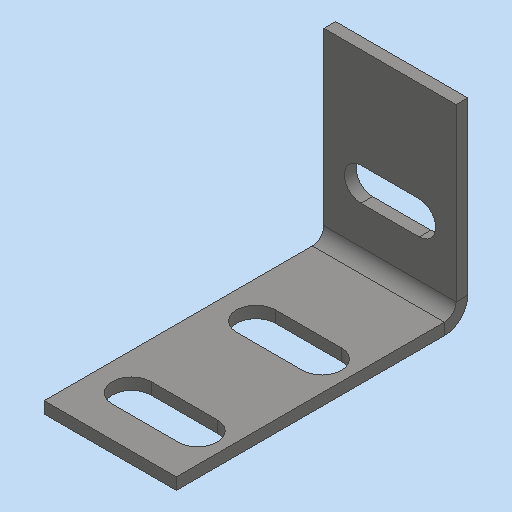
# Autodesk Inventor part: MM0861AN200_G22_108
Saved by Autodesk Inventor 2023.3 (Build 273359000, 359)
## iProperties
Part Number: MM0861AN200_G22_108
Material: 1.4301 X5CrNi18-10
Description: =<RBPARTNOTITLE2>
Document SubType Name: Blech
Designer: Benutzer
Mass: 80.0937 g
Surface Area: 82.8903 cm^2
Volume: 10.203 cm^3
Density: 7.85 g/cm^3
Sheet Metal Rule: Standard_mm
Appearance: Stahl - rostfrei AnP
Vendor: ASW
Flat Pattern Width: 3.4 cm
Flat Pattern Length: 11.9786 cm
Flat Pattern Area: 40.7272 cm^2
Sheet Metal Width: 34,000 mm
Sheet Metal Length: 119,786 mm
Sheet Metal Area: 4072,719 mm^2
RBCHANGEDESCRIPTION1: Erstfreigabe
RBCHANGENO1: 00
RBDOCUMENTTYPE: DRF
RBDOCUMENTVERSION: 00
RBDRAWINGMAINSCALE: 1:1
RBDRAWINGMISSINGSPEC: --
RBDRAWINGVOLUME: --
RBDSV1: 0850
RBGBDETAILS: 43274
RBGBEDGESIN1: +0,5
RBGBEDGESIN2: +0,2
RBGBEDGESOUT1: -0,3
RBGBEDGESOUT2: -0,1
RBMATERIAL: =<Material>
RBMATMEETS: --
RBMATNO: =<Part Number>
RBORGUNITRESPONSIBLE1: AnP/TEF1
RBPARTMADEOF: 50 x 75 x 34 (FM)
RBPARTNO: SIEHE MNR
RBPARTNOTITLE1: manufactured part
RBPARTNOTITLE2: Anfertigungsteil
RBPARTSAFETYINDICATOR: --
RBSURFACE: --
RBSURFACE2: --
RBZEDGESNORM: ISO13715:2002-06
RBZGENDIMCLASS: m
RBZGENDIMNORM: ISO 2768-1:1989-11
RBZGENGEOCLASS: H
RBZGENGEONORM: ISO 2768-2:1989-11
RBZSURFACENORM: ISO13D2:2002-02
RBZTOLERANCENORM: ISO 14405-1:2010-12
AnP_Material: =<Material>
AnP_TemplVers: 20190222
AnP_Kategorie: 1
MaxAbmaße: 50 x 75 x 34 (FM)
Author: Benutzer
Keywords: =<RBPARTMADEOF>
Comments: =<RBSURFACE2>
Revision Number: 01
Autodesk Inventor part; units mm, degrees
ref_plane "YZ Plane" through (0, 0, 0) normal (1, 0, 0) x (0, 1, 0)
ref_plane "XZ Plane" through (0, 0, 0) normal (0, 1, 0) x (-1, 0, 0)
ref_plane "XY Plane" through (0, 0, 0) normal (0, 0, 1) x (1, 0, 0)
sketch "Skizze1" plane through (0, 0, 0) normal (0, 0, 1) x (1, 0, 0)
  line L0 (0, 0) -> (34, 0)
  line L1 (34, 0) -> (34, 75)
  line L2 (34, 75) -> (0, 75)
  line L3 (0, 75) -> (0, 0)
  dimension "d0" = 34
  dimension "d1" = 75
  constraints: 8 end point, 2 parallel, 1 horizontal, 1 perpendicular
  measures "d0" distance of L2.end L1.end
  measures "d1" distance of L1.end L0.end
extrude "Extrusion1" add sketch "Skizze1" along normal blind 3
sketch "Skizze2" plane through (0, 72, 0) normal (0, 1, 0) x (-1, 0, 0)
  line L0 (-34, 0) -> (0, 0)
  line L1 (0, 0) -> (0, 50)
  line L2 (0, 50) -> (-34, 50)
  line L3 (-34, 50) -> (-34, 0)
  constraints: 4 end point, 4 other
edge flange "Lasche1" height 50 angle 90 thickness 3 bend radius 3 thickness toward (0, 1, 0) relief tear relief width 3 relief depth 1.5 edges at (17, 75, 3) wall of the first edge with corners at (34, 72, 0) (0, 72, 0) (0, 72, 50) (34, 72, 50)
bend "Biegung1"
corner "Ecke1"
sketch "Skizze4" plane through (0, 0, 3) normal (0, 0, 1) x (1, 0, 0)
  line L0 (26.5, 45) -> (9.5, 45) construction
  line L1 (26.5, 50) -> (9.5, 50)
  line L2 (9.5, 40) -> (26.5, 40)
  arc A0 (26.5, 40) -> (26.5, 50) centre (26.5, 45) ccw
  arc A1 (9.5, 50) -> (9.5, 40) centre (9.5, 45) ccw
  line L3 (26.5, 13) -> (9.5, 13) construction
  line L4 (26.5, 18) -> (9.5, 18)
  line L5 (9.5, 8) -> (26.5, 8)
  arc A2 (26.5, 8) -> (26.5, 18) centre (26.5, 13) ccw
  arc A3 (9.5, 18) -> (9.5, 8) centre (9.5, 13) ccw
  line L6 (34, 0) -> (34, 69) projected
  point P0 (0, 0)
  point P1 (18, 45)
  point P2 (18, 13)
  dimension "d20" = 17
  dimension "d21" = 10
  dimension "d22" = 10
  dimension "d23" = 16
  constraints: 16 end point, 8 point on circle, 8 tangent, 4 centre point, 3 parallel, 2 midpoint, 2 vertical alignment, 1 horizontal
  measures "d20" distance of L0.start L0.end
  measures "d21" diameter of A1
  measures "d22" diameter of A3
  measures "d23" distance from line of L6 point (18, 45)
extrude "Extrusion3" cut sketch "Skizze4" against normal blind 3
sketch "Skizze5" plane through (0, 72, 50) normal (0, -1, 0) x (1, 0, 0)
  line L0 (9.5, -30) -> (24.5, -30) construction
  line L1 (9.5, -34.25) -> (24.5, -34.25)
  line L2 (24.5, -25.75) -> (9.5, -25.75)
  arc A0 (9.5, -25.75) -> (9.5, -34.25) centre (9.5, -30) ccw
  arc A1 (24.5, -34.25) -> (24.5, -25.75) centre (24.5, -30) ccw
  line L3 (0, -50) -> (34, -50) projected
  line L4 (0, 0) -> (0, -44) projected
  point P0 (17, -30)
  dimension "d26" = 8.5
  dimension "d27" = 20
  dimension "d28" = 17
  dimension "d29" = 15
  constraints: 8 end point, 4 point on circle, 4 tangent, 2 centre point, 1 horizontal, 1 midpoint, 1 parallel
  measures "d26" diameter of A1
  measures "d27" distance from line of L3 point (17, -30)
  measures "d28" distance from line of point (17, -30) L4
  measures "d29" distance of L0.end L0.start
extrude "Extrusion4" cut sketch "Skizze5" against normal blind 3
equation "\"d4\" = BreiteBiegungsfreistellung"
equation "\"d5\" = TiefeBiegungsfreistellung"
equation "\"d6\" = MinimalRest"
equation "\"d7\" = Biegeradius"
equation "\"d10\" = Biegeradius"
equation "\"d11\" = GrößeEckenfreistellung"
equation "\"d12\" = Abstandsgröße"
equation "\"d13\" = JacobiRadiusGröße"
equation "\"d32\" = Stärke"
equation "\"Biegeradius\" = Stärke"
equation "\"BreiteBiegungsfreistellung\" = Stärke"
equation "\"TiefeBiegungsfreistellung\" = 0.5 * Stärke"
equation "\"GrößeEckenfreistellung\" = 4 * Stärke"
equation "\"MinimalRest\" = 2 * Stärke"
equation "\"Übergangsradius\" = Biegeradius"
equation "\"JacobiRadiusGröße\" = Biegeradius"
equation "\"Abstandsgröße\" = Stärke"
equation "\"Stärke\" = 3"
